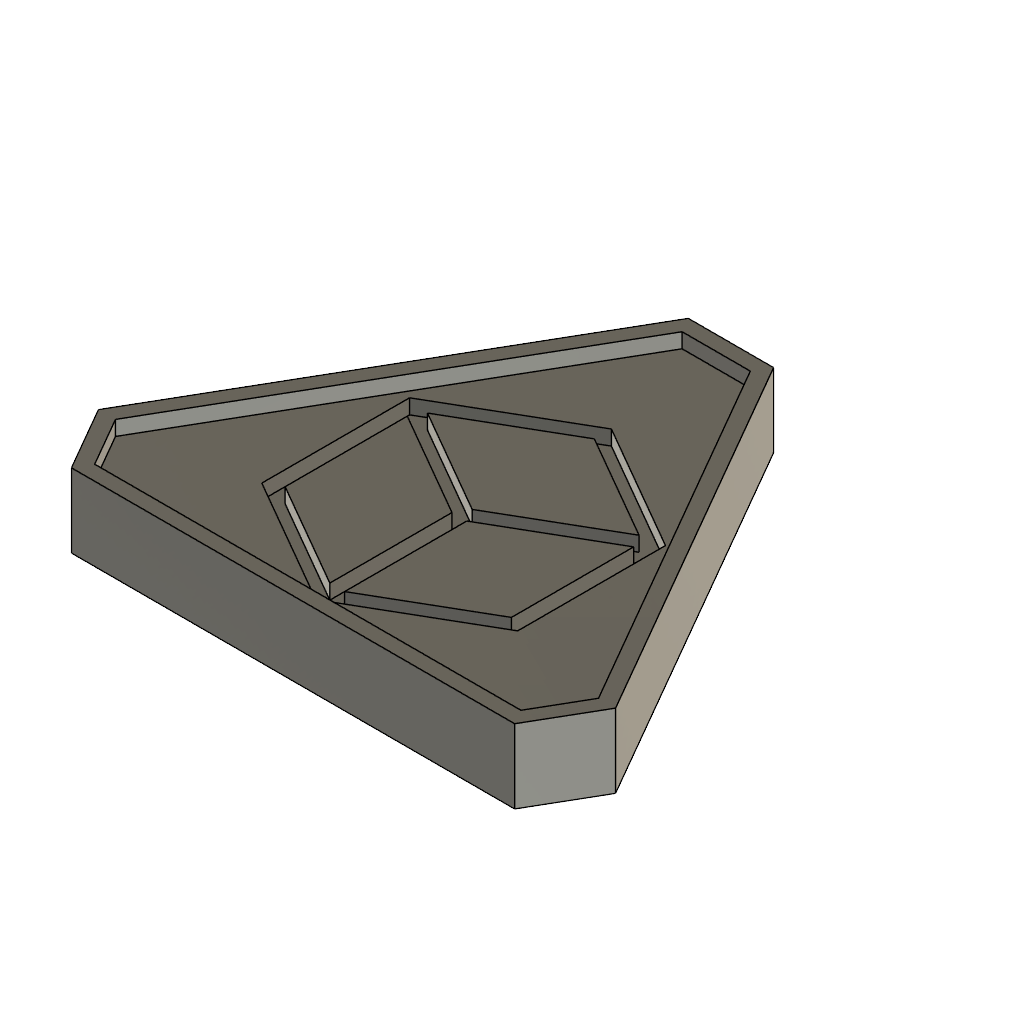
Triangle Piece (Autodesk Fusion 360 design; units mm, degrees)
part number: 2026-10-13-18-31-53-346
Autodesk Fusion 360 part; units mm, degrees
sketch "Sketch1" plane through (0, 0, 0) normal (0, 0, 1) x (1, 0, 0)
  line L0 (-27.4173, -21.7284) -> (-7.4173, -21.7284)
  line L1 (-17.4173, -4.4079) -> (-7.4173, -21.7284)
  line L2 (-27.4173, -21.7284) -> (-17.4173, -4.4079)
  line L3 (-26.1673, -19.5634) -> (-24.9173, -21.7284)
  line L4 (-8.6673, -19.5634) -> (-9.9173, -21.7284)
  line L5 (-18.8607, -6.9079) -> (-15.974, -6.9079)
  line L6 (-25.206, -21.2284) -> (-9.6287, -21.2284)
  line L7 (-8.956, -20.0634) -> (-16.5513, -6.9079)
  line L8 (-18.2834, -6.9079) -> (-25.8787, -20.0634)
  line L9 (-25.59, -19.5634) -> (-24.6287, -21.2284)
  line L10 (-9.2447, -19.5634) -> (-10.206, -21.2284)
  line L11 (-18.572, -7.4079) -> (-16.2626, -7.4079)
  line L12 (-21.7475, -13.4549) -> (-21.7475, -18.4549)
  line L13 (-21.7475, -18.4549) -> (-17.4173, -20.9549)
  line L14 (-17.4173, -20.9549) -> (-13.0872, -18.4549)
  line L15 (-13.0872, -18.4549) -> (-13.0872, -13.4549)
  line L16 (-21.7475, -13.4549) -> (-17.4173, -10.9549)
  line L17 (-17.4173, -10.9549) -> (-13.0872, -13.4549)
  line L18 (-17.4173, -15.9549) -> (-13.0872, -13.4549)
  line L19 (-17.4173, -15.9549) -> (-21.7475, -13.4549)
  line L20 (-17.4173, -15.9549) -> (-17.4173, -20.9549)
  line L21 (-17.4173, -4.4079) -> (-17.4173, -21.7284)
  line L22 (-27.4173, -21.7284) -> (-12.4173, -13.0682)
  line L23 (-7.4173, -21.7284) -> (-22.4173, -13.0682)
  line L24 (-21.2475, -13.7436) -> (-21.2475, -18.1663)
  line L25 (-21.2475, -18.1663) -> (-17.4173, -20.3776)
  line L26 (-17.4173, -20.3776) -> (-13.5872, -18.1663)
  line L27 (-13.5872, -18.1663) -> (-13.5872, -13.7436)
  line L28 (-17.4173, -11.5323) -> (-13.5872, -13.7436)
  line L29 (-21.2475, -13.7436) -> (-17.4173, -11.5323)
  line L30 (-17.6673, -20.8106) -> (-17.6673, -15.8106)
  line L31 (-17.1673, -15.8106) -> (-17.1673, -20.8106)
  line L32 (-21.7475, -13.7436) -> (-17.4173, -16.2436)
  line L33 (-21.4975, -13.3106) -> (-17.1673, -15.8106)
  line L34 (-13.3372, -13.3106) -> (-17.6673, -15.8106)
  line L35 (-13.0872, -13.7436) -> (-17.4173, -16.2436)
  dimension "d4" = 60
  dimension "d5" = 60
  dimension "d6" = 60
  dimension "d11" = 60
  dimension "d13" = 60
  dimension "d15" = 60
  dimension "d17" = 60
  dimension "d18" = 60
  dimension "d19" = 60
  dimension "d20" = 60
  dimension "d21" = 60
  dimension "d22" = 60
  dimension "d26" = 120
  dimension "d27" = 120
  dimension "d29" = 120
  dimension "d30" = 120
  dimension "d33" = 120
  dimension "d34" = 120
  dimension "d39" = 5
  dimension "d40" = 5
  dimension "d41" = 120
  dimension "d42" = 5
  dimension "d43" = 120
  dimension "d44" = 120
  dimension "d45" = 5
  dimension "d46" = 120
  dimension "d47" = 5
  dimension "d50" = -0.5
  dimension "d53" = 60
  dimension "d54" = 60
  dimension "d55" = 60
  dimension "d56" = 60
  dimension "d57" = 0.25
  dimension "d59" = 0.25
  dimension "d60" = 0.25
  dimension "d63" = 20
  dimension "d64" = 20
  dimension "d65" = 20
  dimension "d66" = 0.5
  dimension "d67" = 0.5
  dimension "d68" = 0.5
  dimension "d69" = 0.5
  dimension "d70" = 0.5
  dimension "d71" = 0.5
  dimension "d72" = 5
  constraint horizontal L0
  constraint coincident L2 L3.start
  constraint coincident L0 L3.end
  constraint coincident L1 L4.start
  constraint coincident L0 L4.end
  constraint coincident L2 L5.start
  constraint coincident L1 L5.end
  constraint horizontal L5
  constraint coincident L3 L6.start
  constraint coincident L4 L6.end
  constraint horizontal L6
  constraint coincident L4 L7.start
  constraint coincident L5 L7.end
  constraint coincident L5 L8.start
  constraint coincident L3 L8.end
  constraint coincident L8 L9.start
  constraint coincident L6 L9.end
  constraint parallel L3 L9
  constraint coincident L7 L10.start
  constraint coincident L6 L10.end
  constraint coincident L8 L11.start
  constraint coincident L7 L11.end
  constraint horizontal L11
  constraint vertical L12
  constraint midpoint L0 L21.end
  constraint midpoint L1 L22.end
  constraint midpoint L2 L23.end
  constraint coincident L13 L30.start
  constraint coincident L19 L30.end
  constraint vertical L30
  constraint coincident L18 L31.start
  constraint coincident L14 L31.end
  constraint parallel L30 L31
  constraint coincident L12 L32.start
  constraint coincident L20 L32.end
  constraint coincident L16 L33.start
  constraint coincident L17 L34.start
  constraint coincident L15 L35.start
  constraint coincident L18.start L22
  constraint coincident L18.start L21
  constraint collinear L20 L21
  constraint collinear L18 L22
  measures "d4" angle of L0 L2
  measures "d5" angle of L1 L2
  measures "d6" angle of L0 L1
  measures "d11" angle of L2 L3
  measures "d13" angle of L0 L4
  measures "d15" angle of L2 L5
  measures "d17" angle of L3 L8
  measures "d18" angle of L3 L6
  measures "d19" angle of L4 L6
  measures "d20" angle of L4 L7
  measures "d21" angle of L5 L7
  measures "d22" angle of L5 L8
  measures "d26" angle of L8 L11
  measures "d27" angle of L7 L11
  measures "d29" angle of L7 L10
  measures "d30" angle of L6 L10
  measures "d33" angle of L8 L9
  measures "d34" angle of L6 L9
  measures "d39" distance of L12.start L12.end
  measures "d40" distance of L12.end L13.end
  measures "d41" angle of L12 L13
  measures "d42" distance of L13.end L14.end
  measures "d43" angle of L13 L14
  measures "d44" angle of L14 L15
  measures "d45" distance of L14.end L15.end
  measures "d46" angle of L12 L16
  measures "d47" distance of L12.start L16.end
  measures "d53" angle of L16 L33
  measures "d54" angle of L12 L32
  measures "d55" angle of L17 L34
  measures "d56" angle of L15 L35
  measures "d57" distance of L19 L33
  measures "d59" distance of L18 L35
  measures "d60" distance of L18 L34
  measures "d63" distance of L0.start L1.start
  measures "d64" distance of L0.end L1.start
  measures "d65" distance of L0.start L0.end
  measures "d66" distance of L0 L6
  measures "d67" distance of L1 L7
  measures "d68" distance of L2 L8
  measures "d69" distance of L3 L9
  measures "d70" distance of L4 L10
  measures "d71" distance of L5 L11
  measures "d72" distance of L15.end L16.end
extrude "Extrude1" add sketch "Sketch1" along normal blind 2 contours L0 L3 L6 L21 | L2 L3 L8 L23 | L3 L6 L9 L22 | L3 L8 L9 L22 | L0 L4 L6 L21 | L2 L5 L8 L23 | L6 L9 L13 L21 L22 | L8 L9 L12 L22 L23 | L6 L10 L14 L21 L23 | L8 L11 L16 L21 L23 | L13 L22 L25 L30 | L12 L22 L24 L32 | L4 L6 L10 L23 | L14 L20 L21 L26 L31 | L13 L20 L21 L25 L30 | L5 L8 L11 L21 | L12 L19 L23 L24 L32 | L16 L19 L23 L29 L33 | L22 L24 L32 | L22 L25 L30 | L1 L4 L7 L22 | L4 L7 L10 L23 | L7 L10 L15 L22 L23 | L14 L23 L26 L31 | L20 L21 L25 L30 L32 | L20 L21 L26 L31 L35 | L1 L5 L7 L22 | L5 L7 L11 L21 | L7 L11 L17 L21 L22 | L16 L21 L29 L33 | L19 L23 L29 L33 L34 | L19 L23 L24 L30 L32 | L19 L22 L23 L30 | L20 L21 L22 L32 | L15 L23 L27 L35 | L23 L26 L31 | L20 L21 L23 L35 | L17 L21 L28 L34 | L21 L29 L33 | L19 L21 L23 L34 | L18 L21 L22 L33 | L18 L22 L23 L31 | L15 L18 L22 L27 L35 | L23 L27 L35 | L18 L22 L27 L31 L35 | L17 L18 L22 L28 L34 | L21 L28 L34 | L18 L22 L28 L33 L34 makes body 1
extrude "Extrude2" add sketch "Sketch1" along normal blind 2.5 separate body contours L0 L3 L6 L21 | L2 L3 L8 L23 | L3 L6 L9 L22 | L3 L8 L9 L22 | L0 L4 L6 L21 | L2 L5 L8 L23 | L4 L6 L10 L23 | L5 L8 L11 L21 | L1 L4 L7 L22 | L4 L7 L10 L23 | L1 L5 L7 L22 | L5 L7 L11 L21 makes body 2
move_body "Move1" bodies 1 2 to x (1, 0, 0) y (0, 1, 0) z (0, 0, 1) at (0, 0, -2)
extrude "Extrude3" cut sketch "Sketch1" against normal blind 0.5 contours L13 L22 L25 L30 | L12 L22 L24 L32 | L14 L20 L21 L26 L31 | L13 L20 L21 L25 L30 | L12 L19 L23 L24 L32 | L16 L19 L23 L29 L33 | L14 L23 L26 L31 | L20 L21 L25 L30 L32 | L20 L21 L26 L31 L35 | L16 L21 L29 L33 | L19 L23 L29 L33 L34 | L19 L23 L24 L30 L32 | L19 L22 L23 L30 | L20 L21 L22 L32 | L15 L23 L27 L35 | L20 L21 L23 L35 | L17 L21 L28 L34 | L19 L21 L23 L34 | L18 L21 L22 L33 | L18 L22 L23 L31 | L15 L18 L22 L27 L35 | L18 L22 L27 L31 L35 | L17 L18 L22 L28 L34 | L18 L22 L28 L33 L34 bodies 1
move_body "Move2" bodies 1 2 to x (1, 0, 0) y (0, 1, 0) z (0, 0, 1) at (0, 0, 2)
combine "Combine1" operation add target body 1 tool bodies 2
scale "Scale1" factor 1.794872 about (-17.4173, -15.9549, 0) bodies 1
equation "d39 = d47"
equation "d40 = d47"
equation "d42 = d47"
equation "d45 = d47"
equation "d73 = 70 / 39"
